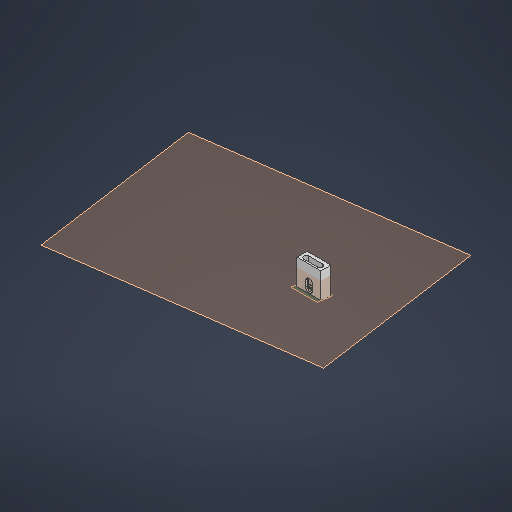
# Autodesk Inventor part: support_aimant_chargeur
Saved by Autodesk Inventor 2026.1 (Build 301233020, 233B)
## iProperties
Created: 2026-06-08
Part Number: support_aimant_chargeur
Material: Générique
Document SubType Name: Modeling
Designer: matpo
Density: 1 g/cm^3
Appearance: Par défaut
Author: matpo
Autodesk Inventor part; units mm, degrees
ref_plane "YZ Plane" through (0, 0, 0) normal (1, 0, 0) x (0, 1, 0)
ref_plane "XZ Plane" through (0, 0, 0) normal (0, 1, 0) x (-1, 0, 0)
ref_plane "XY Plane" through (0, 0, 0) normal (0, 0, 1) x (1, 0, 0)
ref_plane "Plan de construction1" through (-101.815087, 5, 75.041912) normal (0, 1, 0) x (-0.9903362, 0, 0.1386876)
sketch "Esquisse1" plane through (-101.815087, 5, 75.041912) normal (0, 1, 0) x (-0.9903362, 0, 0.1386876)
  line L0 (-137.395137, -52.292252) -> (-135.34256, -37.635276)
  line L1 (-110.794747, -57.027154) -> (-136.543488, -53.421276)
  line L2 (-107.613147, -41.518529) -> (-109.665724, -56.175505)
  line L3 (-134.213536, -36.783628) -> (-108.464795, -40.389506)
  arc A0 (-110.794747, -57.027154) -> (-109.665724, -56.175505) centre (-110.65606, -56.036817) ccw
  arc A1 (-137.395137, -52.292252) -> (-136.543488, -53.421276) centre (-136.4048, -52.430939) ccw
  arc A2 (-107.613147, -41.518529) -> (-108.464795, -40.389506) centre (-108.603483, -41.379842) ccw
  arc A3 (-134.213536, -36.783628) -> (-135.34256, -37.635276) centre (-134.352224, -37.773964) ccw
  line L4 (-136.571225, -53.619343) -> (-110.822485, -57.225221)
  line L5 (-138.690585, -54.332304) -> (-136.471584, -38.486925)
  line L6 (-106.761498, -42.647553) -> (-108.9805, -58.492932)
  arc A4 (-104.503451, -40.944256) -> (-106.761498, -42.647553) centre (-104.780826, -42.924929) ccw
  arc A5 (-136.471584, -38.486925) -> (-138.174881, -36.228877) centre (-138.452256, -38.20955) ccw
  arc A6 (-130.232668, -44.409419) -> (-131.064794, -50.351436) centre (-130.648731, -47.380428) ccw
  line L7 (-131.064794, -50.351436) -> (-115.219415, -52.570438)
  line L8 (-114.38729, -46.628421) -> (-130.232668, -44.409419)
  arc A7 (-115.219415, -52.570438) -> (-114.38729, -46.628421) centre (-114.803352, -49.599429) ccw
  point P0 (-135.203872, -36.64494)
  point P1 (-107.474459, -40.528193)
  point P2 (-108.9805, -58.492932)
  point P3 (-115.219415, -52.570438)
  point P4 (-131.064794, -50.351436)
  dimension "d5" = 1
  dimension "d17" = 0.2
  dimension "d18" = 1
  dimension "d19" = 1
  constraints: 8 end point, 8 point on circle, 8 tangent, 5 point on line, 4 centre point, 3 equal radius, 1 parallel, 2 other
  measures "d5" radius of A0
  measures "d17" distance between parallel lines of L1 L4
extrude "Extrusion1" add sketch "Esquisse1" along normal blind 10 and the other way blind 25
sketch "Esquisse4" plane through (26, 15, 3.2) normal (0, 0, -1) x (-1, 0, 0)
  line L0 (18.9, -23.6) -> (7.1, -23.6) projected
  arc A0 (18.9, -23.6) -> (18.9, -20.4) centre (18.9, -22) ccw projected
  line L1 (7.1, -20.4) -> (18.9, -20.4) projected
  arc A1 (7.1, -20.4) -> (7.1, -23.6) centre (7.1, -22) ccw projected
  line L2 (26, -35) -> (26, 0) projected
  line L3 (0, 0) -> (26, 0) projected
  line L4 (0, -35) -> (0, 0) projected
  line L5 (26, -35) -> (0, -35) projected
  line L6 (13, -18.6) -> (13, -25.4) construction
  line L7 (11.4, -18.6) -> (11.4, -25.4)
  line L8 (14.6, -25.4) -> (14.6, -18.6)
  arc A2 (14.6, -18.6) -> (11.4, -18.6) centre (13, -18.6) ccw
  arc A3 (11.4, -25.4) -> (14.6, -25.4) centre (13, -25.4) ccw
  line L9 (7.1, -22) -> (18.9, -22) construction
  point P0 (26, -15)
  point P1 (13, -22)
  point P2 (13, -22)
  point P3 (13, -27)
  point P4 (13, -17)
  dimension "d20" = 3.2
  dimension "d21" = 10
  constraints: 10 end point, 6 point on circle, 4 tangent, 2 centre point, 2 midpoint, 1 coincident, 1 horizontal, 1 parallel, 1 perpendicular
  measures "d20" diameter of A3
  measures "d21" distance of point (13, -27) point (13, -17)
extrude "Extrusion4" cut sketch "Esquisse4" against normal up to surface (3.8 mm away) contours L8 A3 L7 L0 | L0 L7 L1 L8 | L1 L7 A2 L8
sketch "Esquisse3" plane through (0, 15, 20) normal (0, 0, 1) x (1, 0, 0)
  arc A0 (11.4, -25.4) -> (14.6, -25.4) centre (13, -25.4) ccw projected
  line L0 (11.4, -18.6) -> (11.4, -25.4) projected
  line L1 (14.6, -25.4) -> (14.6, -18.6) projected
  arc A1 (14.6, -18.6) -> (11.4, -18.6) centre (13, -18.6) ccw projected
  line L2 (17, -18.6) -> (17, -25.4)
  arc A2 (9, -25.4) -> (17, -25.4) centre (13, -25.4) ccw
  line L3 (9, -25.4) -> (9, -18.6)
  arc A3 (17, -18.6) -> (9, -18.6) centre (13, -18.6) ccw
  point P0 (0, -15)
  dimension "d24" = 8
  constraints: 4 end point, 4 point on circle, 2 centre point, 3 other
  measures "d24" distance between parallel lines of L3 L2
extrude "Extrusion3" cut sketch "Esquisse3" against normal up to surface (7 mm away) contours L0 A1 L1 A0 | L2 A2 L3 A3
sketch "Esquisse5" plane through (27, -20, 4.2) normal (1, 0, 0) x (0, 0, -1)
  line L0 (9.226698, 0.769087) -> (-32.8, 6.5)
  line L1 (-15.8, 0) -> (-15.8, 35)
  line L2 (1, 0) -> (1, 35)
  line L3 (0, 0) -> (-14.8, 0)
  line L4 (-15.8, 0) -> (-14.8, 0)
  line L5 (9.415857, 2.156249) -> (-32.610842, 7.887162)
  line L6 (-15.8, 5.594775) -> (-15.8, 0)
  line L7 (-15.8, 0) -> (1, 0)
  line L8 (1, 0) -> (1, 3.303866)
  point P0 (4.2, 20)
  dimension "d25" = 1.4
  constraints: 8 end point, 4 point on line, 1 parallel
  measures "d25" distance between parallel lines of L0 L5
extrude "Extrusion5" cut sketch "Esquisse5" against normal through all
ref_plane "Plan de construction2" through (0, -13.414395, 19.864887) normal (0, -0.9908302, 0.1351132) x (1, 0, 0)
sketch "Esquisse7" plane through (0, -13.414395, 19.864887) normal (0, -0.9908302, 0.1351132) x (1, 0, 0)
  ellipse E0 centre (21, -10.092547) end of major axis (21, -13.120311) minor radius 3 (21, -13.120311) -> (21, -7.064783) ccw
  line L0 (5, -13.120311) -> (21, -13.120311)
  ellipse E1 centre (5, -10.092547) end of major axis (5, -7.064783) minor radius 3 (5, -7.064783) -> (5, -13.120311) ccw
  line L1 (21, -7.064783) -> (5, -7.064783)
  ellipse E2 centre (26, -1.009255) end of major axis (26, 0) minor radius 1 (27, -1.009255) -> (26, 0) ccw
  line L2 (0, 0) -> (26, 0)
  ellipse E3 centre (0, -1.009255) end of major axis (0, 0) minor radius 1 (0, 0) -> (-1, -1.009255) ccw
  line L3 (-1, -15.946224) -> (-1, -1.009255)
  ellipse E4 centre (0, -15.946224) end of major axis (0, -16.955479) minor radius 1 (-1, -15.946224) -> (0, -16.955479) ccw
  line L4 (26, -16.955479) -> (0, -16.955479)
  ellipse E5 centre (26, -15.946224) end of major axis (26, -16.955479) minor radius 1 (26, -16.955479) -> (27, -15.946224) ccw
  line L5 (27, -1.009255) -> (27, -15.946224)
  line L6 (5, -12.292547) -> (21, -12.292547)
  line L7 (21, -7.892547) -> (5, -7.892547)
  spline S0 degree 5 poles (5, -7.892527) (4.612932, -7.892559) (4.225908, -7.979969) (3.865104, -8.154549) (3.078386, -8.788283) (2.723434, -9.768113) (2.723434, -10.416981) (3.078386, -11.396811) (3.865104, -12.030545) (4.225908, -12.205125) (4.612932, -12.292535) (5, -12.292567) knots 0 0 0 0 0 0 0.28180372 0.28180372 0.28180372 0.71819628 0.71819628 0.71819628 1 1 1 1 1 1
  spline S1 degree 5 poles (21, -12.292567) (21.387068, -12.292535) (21.774092, -12.205125) (22.134896, -12.030545) (22.921614, -11.396811) (23.276566, -10.416981) (23.276566, -9.768113) (22.921614, -8.788283) (22.134896, -8.154549) (21.774092, -7.979969) (21.387068, -7.892559) (21, -7.892527) knots 0 0 0 0 0 0 0.28180372 0.28180372 0.28180372 0.71819629 0.71819629 0.71819629 1 1 1 1 1 1
  point P0 (0, -17.870267)
  dimension "d29" = 4.4
  constraints: 4 end point, 3 parallel, 2 vertical alignment, 10 other
  measures "d29" distance between parallel lines of L6 L7
extrude "Extrusion6" add sketch "Esquisse7" against normal blind 2 contours L0 E1 L1 E0
sketch "Esquisse8" plane through (0, -14.405225, 20) normal (0, -0.9908302, 0.1351132) x (1, 0, 0)
  ellipse E0 centre (5, -10.092547) end of major axis (5, -7.064783) minor radius 3 (5, -7.064783) -> (5, -13.120311) ccw
  line L0 (21, -7.064783) -> (5, -7.064783)
  ellipse E1 centre (21, -10.092547) end of major axis (21, -13.120311) minor radius 3 (21, -13.120311) -> (21, -7.064783) ccw
  line L1 (5, -13.120311) -> (21, -13.120311)
  point P0 (0, -17.870267)
  constraints: 2 other
extrude "Extrusion7" cut sketch "Esquisse8" against normal blind 1
sketch "Esquisse9" plane through (5, 15, 7) normal (0, 0, 1) x (1, 0, 0)
  arc A0 (9.6, -18.6) -> (6.4, -18.6) centre (8, -18.6) ccw projected
  arc A1 (6.4, -25.4) -> (9.6, -25.4) centre (8, -25.4) ccw projected
  line L0 (6.4, -18.6) -> (6.4, -25.4) projected
  line L1 (9.6, -25.4) -> (9.6, -18.6) projected
  arc A2 (10.5, -18.6) -> (5.5, -18.6) centre (8, -18.6) ccw
  line L2 (5.5, -18.6) -> (5.5, -25.4)
  arc A3 (5.5, -25.4) -> (10.5, -25.4) centre (8, -25.4) ccw
  line L3 (10.5, -25.4) -> (10.5, -18.6)
  point P0 (-5, -15)
  point P1 (5.5, -22)
  point P2 (10.5, -22)
  dimension "d34" = 5
  constraints: 4 end point, 4 point on circle, 2 centre point, 2 midpoint, 3 other
  measures "d34" distance of point (5.5, -22) point (10.5, -22)
extrude "Extrusion8" cut sketch "Esquisse9" against normal blind 1.5
sketch "Esquisse10" plane through (0, 15, 20) normal (0, 0, 1) x (1, 0, 0)
  line L0 (0, -29.405225) -> (26, -29.405225)
  line L1 (26, -29.405225) -> (26, 0)
  line L2 (0, 0) -> (26, 0)
  line L3 (0, -29.405225) -> (0, 0)
  arc A0 (9, -25.4) -> (17, -25.4) centre (13, -25.4) ccw
  line L4 (9, -25.4) -> (9, -18.6)
  arc A1 (17, -18.6) -> (9, -18.6) centre (13, -18.6) ccw
  line L5 (17, -18.6) -> (17, -25.4)
  line L6 (-9, -56.2) -> (35, -56.2)
  line L7 (35, -56.2) -> (35, 19)
  line L8 (35, 19) -> (-9, 19)
  line L9 (-9, 19) -> (-9, -56.2)
  arc A2 (14.6, -18.6) -> (11.4, -18.6) centre (13, -18.6) ccw
  line L10 (-9, -56.2) -> (35, 19) construction
  line L11 (35, -56.2) -> (-9, 19) construction
  point P0 (0, -15)
  constraints: 12 end point, 2 midpoint, 2 parallel, 1 horizontal, 1 perpendicular
extrude "Extrusion9" cut sketch "Esquisse10" against normal blind 5 contours L3 L2 L1 L0 | L9 L8 L7 L6
equation "\"d19\" = d18"
